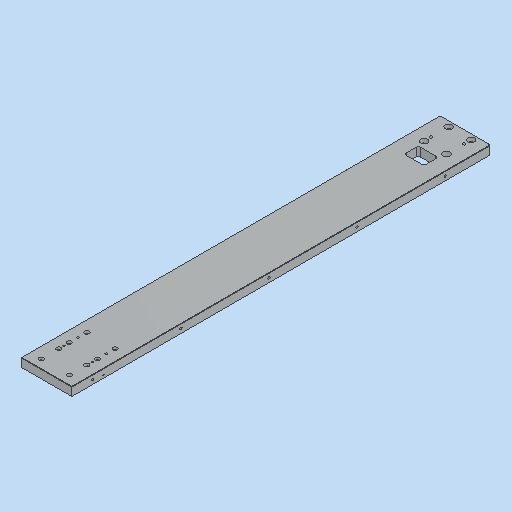
# Autodesk Inventor part: MM0948AN120_G01_110
Saved by Autodesk Inventor 2023.3 (Build 273359000, 359)
## iProperties
Part Number: MM0948AN120_G01_110
Material: 3.1645 AlCu4PbMgMn - AW 2007
Description: =<RBPARTNOTITLE2>
Document SubType Name: Modeling
Designer: ric7an
Mass: 1429.48 g
Surface Area: 1054.1 cm^2
Volume: 501.573 cm^3
Density: 2.85 g/cm^3
Appearance: Aluminium AnP
Created: 2023-03-23
RBDOCUMENTTYPE: DRF
RBDOCUMENTVERSION: 00
RBDRAWINGMAINSCALE: 1:1
RBDRAWINGMISSINGSPEC: --
RBDRAWINGVOLUME: --
RBGBEDGESIN1: +0,5
RBGBEDGESIN2: +0,2
RBGBEDGESOUT1: -0,3
RBGBEDGESOUT2: -0,1
RBMATERIAL: =<Material>
RBMATMEETS: --
RBMATNO: =<Part Number>
RBPARTMADEOF: 12 x 595 x 72 (FM)
RBPARTNO: SIEHE MNR
RBPARTNOTITLE1: manufactured part
RBPARTNOTITLE2: Anfertigungsteil
RBPARTSAFETYINDICATOR: --
RBSURFACE: anodised black
RBSURFACE2: eloxiert schwarz
RBZEDGESNORM: ISO13715:2002-06
RBZGENDIMCLASS: m
RBZGENDIMNORM: ISO 2768-1:1989-11
RBZGENGEOCLASS: H
RBZGENGEONORM: ISO 2768-2:1989-11
RBZSURFACENORM: ISO13D2:2002-02
RBZTOLERANCENORM: ISO 14405-1:2010-12
AnP_Material: =<Material>
AnP_TemplVers: 20190222
AnP_Kategorie: 1
MaxAbmaße: 12 x 595 x 72 (FM)
AnP_Kommentar_aktuell: =<Comments>
AnP_Material_aktuell: =<Material>
Author: FH/Wi
Keywords: =<RBPARTMADEOF>
Comments: =<RBSURFACE2>
Revision Number: 01
Autodesk Inventor part; units mm, degrees
ref_plane "YZ Plane" through (0, 0, 0) normal (1, 0, 0) x (0, 1, 0)
ref_plane "XZ Plane" through (0, 0, 0) normal (0, 1, 0) x (-1, 0, 0)
ref_plane "XY Plane" through (0, 0, 0) normal (0, 0, 1) x (1, 0, 0)
sketch "Skizze1" plane through (0, 0, 0) normal (0, 0, 1) x (1, 0, 0)
  line L0 (-36, 595) -> (36, 595)
  line L1 (36, 595) -> (36, 0)
  line L2 (36, 0) -> (-36, 0)
  line L3 (-36, 0) -> (-36, 595)
  line L4 (0, 714) -> (0, -119) projected
  line L5 (-50.4, 0) -> (50.4, 0) projected
  point P0 (0, 0)
  dimension "d0" = 72
  dimension "d1" = 595
  constraints: 8 end point, 2 parallel, 1 collinear, 1 horizontal, 1 perpendicular, 1 other
  measures "d0" distance of L0.start L0.end
  measures "d1" distance of L0.end L1.end
extrude "Extrusion1" add sketch "Skizze1" along normal blind 12
sketch "Skizze6" plane through (0, 0, 0) normal (0, 0, -1) x (-1, 0, 0)
  line L0 (0, -119) -> (0, 714) projected
  line L1 (-50.4, 0) -> (50.4, 0) projected
  line L2 (36, 595) -> (-36, 595) projected
  point P0 (0, 0)
  point P1 (-16, 587)
  point P2 (-16, 552)
  point P3 (16, 552)
  point P4 (16, 587)
  dimension "d28" = 32
  dimension "d29" = 35
  dimension "d30" = 8
  constraints: 2 symmetric about line, 1 vertical alignment
  measures "d28" distance of point (16, 587) point (-16, 587)
  measures "d29" distance of point (16, 552) point (16, 587)
  measures "d30" distance from line of L2 point (16, 587)
hole "Bohrung3" at (-16, 552, 0) at (16, 552, 0) at (16, 587, 0) at (-16, 587, 0) direction (0, 0, 1) diameter 5.5 end through all counterbore diameter 10 counterbore depth 5.7 clearance for "Inbusschraube ISO 4762  versenkt" size "M5" standard "ISO"
sketch "Skizze7" plane through (0, 0, 0) normal (0, 0, -1) x (-1, 0, 0)
  circle A0 centre (16, 552) radius 5 projected
  circle A1 centre (-16, 552) radius 5 projected
  point P0 (0, 0)
  point P1 (16, 577)
  point P2 (-16, 562)
  dimension "d38" = 15
  dimension "d39" = 10
  constraints: 2 vertical alignment
  measures "d38" vertical distance of point (-16, 562) point (16, 577)
  measures "d39" distance of A1.centre point (-16, 562)
hole "Bohrung4" at (-16, 577, 0) at (16, 562, 0) direction (0, 0, 1) diameter 4 end through all
chamfer "Fase1" distance 2 angle 45 2 edges at (36, 595, 6) (-36, 595, 6)
sketch "Skizze13" plane through (-36, 282, 0) normal (-1, 0, 0) x (0, 0, 1)
  line L0 (12, 313) -> (0, 313) projected
  line L1 (12, 313) -> (12, -282) projected
  line L2 (0, -282) -> (12, -282) projected
  line L3 (6, -252) -> (6, -2)
  line L4 (6, -2) -> (6, 248)
  point P0 (12, 311)
  point P1 (6, 123)
  point P2 (6, -127)
  dimension "d104" = 500
  dimension "d106" = 6
  dimension "d114" = 250
  dimension "d180" = 530
  constraints: 4 end point, 2 midpoint, 2 vertical alignment, 1 collinear, 1 parallel
  measures "d104" distance of L3.start L4.end
  measures "d106" distance from line of L1 L4.end
  measures "d114" distance of L3.start L3.end
  measures "d180" distance from line of L2 L4.end
hole "Bohrung9" at (-36, 530, 6) at (-36, 30, 6) at (-36, 280, 6) at (-36, 155, 6) at (-36, 405, 6) direction (1, 0, 0) diameter 3.242 depth 11.8 tip angle 118 thread size "M4x0.7" designation "M4" class "6H" standard "ISO Metric profile"
mirror "Spiegeln1" about plane through (0, 0, 0) normal (1, 0, 0) of "Bohrung9"
sketch "Skizze16" plane through (0, 296.2726, 0) normal (0, 0, -1) x (-1, 0, 0)
  line L0 (0, 50.0691) -> (0, -296.2726)
  line L1 (-43.9384, -251.2726) -> (54.0616, -251.2726)
  line L2 (-36, -296.2726) -> (36, -296.2726) projected
  point P0 (0, 0)
  point P1 (-20, -218.7726)
  point P2 (-20, -283.7726)
  point P3 (20, -283.7726)
  point P4 (20, -218.7726)
  point P5 (-20, -243.7726)
  point P6 (-20, -258.7726)
  point P7 (20, -258.7726)
  point P8 (20, -243.7726)
  dimension "d138" = 15
  dimension "d140" = 65
  dimension "d139" = 40
  dimension "d147" = 45
  constraints: 4 symmetric about line, 3 vertical alignment, 2 end point, 1 midpoint, 1 vertical, 3 other
  measures "d138" distance of point (20, -258.773) point (20, -243.773)
  measures "d140" distance of point (20, -283.773) point (20, -218.773)
  measures "d139" distance of point (20, -218.773) point (-20, -218.773)
hole "Bohrung12" at (20, 77.5, 0) at (20, 12.5, 0) at (-20, 12.5, 0) at (-20, 77.5, 0) at (20, 52.5, 0) at (20, 37.5, 0) at (-20, 37.5, 0) at (-20, 52.5, 0) direction (0, 0, 1) diameter 3.4 end through all counterbore diameter 6.5 counterbore depth 3.4
chamfer "Fase4" distance 0.5 angle 45 6 edges at (-36, 296.5, 0) (-35, 594, 0) (0, 595, 0) (35, 594, 0) (36, 296.5, 0) (0, 0, 0)
sketch "Skizze17" plane through (0, 297.856, 0) normal (0, 0, -1) x (-1, 0, 0)
  line L0 (0, -291.0168) -> (0, -214.6951)
  line L1 (-49, -252.856) -> (49, -252.856)
  circle A0 centre (-20, -220.356) radius 3.25 projected
  circle A1 centre (20, -285.356) radius 3.25 projected
  line L2 (-20, -220.356) -> (20, -285.356)
  point P0 (0, 0)
  point P1 (-20, -232.856)
  point P2 (-20, -272.856)
  point P3 (20, -272.856)
  point P4 (20, -232.856)
  point P5 (0, -252.856)
  dimension "d149" = 40
  constraints: 4 end point, 3 vertical alignment, 2 midpoint, 2 symmetric about line, 1 equal length, 1 vertical, 4 other
  measures "d149" distance of point (20, -272.856) point (20, -232.856)
hole "Bohrung13" at (20, 65, 0) at (-20, 65, 0) direction (0, 0, 1) diameter 3 end through all
sketch "Skizze18" plane through (0, 298.2973, 0) normal (0, 0, 1) x (1, 0, 0)
  circle A0 centre (-20, -245.7973) radius 1.7 projected
  circle A1 centre (20, -260.7973) radius 1.7 projected
  line L0 (-20, -245.7973) -> (20, -245.7973)
  line L1 (20, -245.7973) -> (20, -260.7973)
  line L2 (20, -260.7973) -> (-20, -260.7973)
  line L3 (-20, -260.7973) -> (-20, -245.7973)
  point P0 (-20, -253.2973)
  point P1 (20, -253.2973)
  point P2 (-20, -253.2973)
  point P3 (20, -253.2973)
  constraints: 8 end point, 2 coincident, 2 midpoint, 2 parallel, 1 horizontal, 1 perpendicular
hole "Bohrung14" at (-20, 45, 0) at (20, 45, 0) direction (0, 0, 1) diameter 2.459 end through all thread size "M3x0.5" designation "M3" class "6H" standard "ISO Metric profile"
sketch "Skizze19" plane through (0, 297.5, 12) normal (0, 0, 1) x (1, 0, 0)
  circle A0 centre (-20, -252.5) radius 1.2295 projected
  circle A1 centre (20, -252.5) radius 1.2295 projected
  point P0 (0, 0)
  constraints: 2 coincident
hole "Bohrung15" at (-20, 45, 12) at (20, 45, 12) direction (0, 0, -1) diameter 5 depth 0.7
sketch "Skizze22" plane through (-36, 0, 12) normal (-1, 0, 0) x (0, 0, 1)
  line L0 (-12, 43.7705) -> (-12, 46.2295) projected
  line L1 (0, 47.5) -> (0, 42.5) projected
  line L2 (-12, 592.7929) -> (-12, 0.5) projected
  point P0 (-12, 0)
  point P1 (-4, 45)
  point P2 (-12, 45)
  dimension "d188" = 8
  constraints: 1 horizontal alignment, 1 midpoint
  measures "d188" distance from line of point (-4, 45) L2
hole "Bohrung18" at (-36, 45, 8) direction (1, 0, 0) diameter 2.459 end up to surface thread size "M3x0.5" designation "M3" class "6H" standard "ISO Metric profile"
sketch "Skizze23" plane through (36, 0, 12) normal (1, 0, 0) x (0, 0, -1)
  circle A0 centre (4, 45) radius 1.2295 projected
  point P0 (12, 0)
hole "Bohrung19" at (36, 45, 8) direction (-1, 0, 0) diameter 2.459 end up to surface thread size "M3x0.5" designation "M3" class "6H" standard "ISO Metric profile"
sketch "Skizze24" plane through (0, 0, 0) normal (0, 0, -1) x (-1, 0, 0)
  line L0 (-14, 542) -> (14, 542)
  line L1 (14, 542) -> (14, 522)
  line L2 (14, 522) -> (-14, 522)
  line L3 (-14, 522) -> (-14, 542)
  line L4 (0, -119) -> (0, 714) projected
  line L5 (-50.4, 0) -> (50.4, 0) projected
  line L6 (34, 595) -> (-34, 595) projected
  point P0 (0, 0)
  dimension "d203" = 53
  dimension "d204" = 20
  dimension "d205" = 28
  constraints: 8 end point, 2 parallel, 1 horizontal, 1 perpendicular, 1 other
  measures "d203" distance between parallel lines of L6 L0
  measures "d204" distance of L0.end L1.end
  measures "d205" distance of L1.end L2.end
extrude "Extrusion5" cut sketch "Skizze24" against normal through all
fillet "Rundung4" radius 3 4 edges at (14, 542, 6) (14, 522, 6) (-14, 522, 6) (-14, 542, 6)
equation "\"d114\" = 0.5 * d104"
